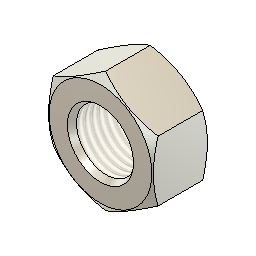
SFX-100 (Autodesk Fusion 360 archive; units mm, degrees)
design "육각 너트 DIN 934 - M12 x 1.25 강 6 플레인"
description: 육각 너트 DIN 934 - M12 x 1.25
part number: DIN 934 - M12 x 1.25 강 6 플레인
Autodesk Fusion 360 part; units mm, degrees
sketch "Sketch1" plane through (0, 0, 0) normal (0, 1, 0) x (1, 0, 0)
  line L0 (0, 0) -> (0, -10)
  line L1 (-6, 0) -> (-9.31, 0)
  line L2 (-9.31, 0) -> (-10.9725, -0.9598)
  line L3 (-10.9725, -0.9598) -> (-10.9725, -9.0402)
  line L4 (-10.9725, -9.0402) -> (-9.31, -10)
  line L5 (-9.31, -10) -> (-6, -10)
  line L6 (-6, -10) -> (-6, 0)
  dimension "d121" = 12
  dimension "d122" = 30
  dimension "d123" = 30
  dimension "d128" = 21.945
  dimension "d172" = 18.62
  dimension "d176" = 10
  constraint vertical L0
  constraint coincident L0 L0.end
  constraint coincident origin L0
  constraint horizontal L1
  constraint perpendicular L1 L3
  constraint perpendicular L3 L5
  constraint perpendicular L5 L6
  constraint coincident L0.start L1
  constraint coincident L0.start origin
  constraint coincident L0.end L5
  constraint vertical L1.end L4.end
  measures "d122" angle of L1 L2
  measures "d123" angle of L4 L5
  measures "d176" distance of L1.start L5
revolve "Revolve1" add sketch "Sketch1" angle 360 about axis through (0, 0, 0) along (0, 0, 1)
sketch "Sketch8" plane through (0, 0, 10) normal (0, 0, 1) x (1, 0, 0)
  line L0 (0, 0) -> (-19, 0) construction
  line L1 (-9.5, -5.4905) -> (-9.5, 5.4905)
  circle A0 centre (0, 0) radius 6
  circle A1 centre (0, 0) radius 10.9725
  dimension "d114" = 9.5
  constraint horizontal L0
  constraint perpendicular L0 L1
  constraint midpoint L0 L1
  constraint coincident L0.start A0.centre
  constraint coincident L1.end A1
  measures "d114" distance of L0.start L1
extrude "Extrude5" cut sketch "Sketch8" against normal blind 10 contours L1 A1 picked at (-9.7376, 1.3373)
pattern_circular "C-Pattern2" count 6 over 360 about axis through (0, 0, 1.75) along (0, 0, 1) of "Extrude5"
thread "Thread3" "ISO Metric profile 12.0 M12x1.25 M12x1.25 6H" major diameter 12.18 minor diameter 10.7795 pitch 1.25 angle 60 resizes the face on face at (-5.9702, 0.5974, 6.6667)
sketch "Sketch12" plane through (0, 0, 0) normal (0, 1, 0) x (1, 0, 0)
  line L0 (5.3898, -10) -> (-5.3898, -10)
  line L1 (9.31, -10) -> (-9.31, -10)
  line L2 (9.31, 0) -> (-9.31, 0)
  line L3 (5.3898, 0) -> (-5.3898, 0)
  line L4 (-6, 0) -> (0, 0)
  line L5 (-3.1132, -5) -> (-6, 0)
  line L6 (-6, -10) -> (0, -10)
  line L7 (-3.1132, -5) -> (-6, -10)
  line L8 (0, 0) -> (0, -10)
  dimension "d165" = 60
  dimension "d169" = 60
  dimension "d177" = 6
  constraint horizontal L4
  constraint collinear L1 L6
  constraint coincident L5.start L7.start
  constraint vertical L4.start L6.start
  constraint coincident L1 L6.end
  constraint coincident L6.end L8.end
  constraint coincident L4.end L8.start
  measures "d165" angle of L2 L5
  measures "d169" angle of L6 L7
  measures "d177" distance of L4.start L8
revolve "Revolve3" cut sketch "Sketch12" angle 360 about axis through (0, 0, 1.75) along (0, 0, 1)
equation "adsk_nheig = 10.00 mm"
equation "adsk_maxdia = 21.945 mm"
equation "adsk_nomdia = 12.00 mm"
equation "d89 = -adsk_nheig"
equation "adsk_waflat = 19.00 mm"
equation "d114 = adsk_waflat / 2"
equation "adsk_chamang1 = 30.00 deg"
equation "adsk_chamang2 = 30.00 deg"
equation "d121 = adsk_nomdia"
equation "d122 = adsk_chamang1"
equation "d123 = adsk_chamang2"
equation "d128 = adsk_maxdia"
equation "d163 = adsk_nheig"
equation "adsk_beardia = adsk_waflat * 0.98"
equation "d172 = adsk_beardia"
equation "d176 = adsk_nheig"
equation "d177 = adsk_nomdia * 0.5"

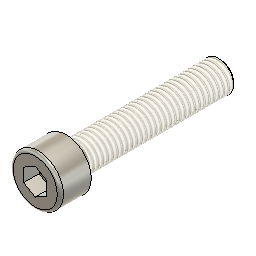
design "브로치 육각 소켓 머리 캡 나사 ANSI B18.3.1M - M8x1.25 x 40 강철 등급 2 플레인"
description: 브로치 육각 소켓 머리 캡 나사 ANSI B18.3.1M - M8x1.25 x 40
part number: BSHCS ANSI B18.3.1M - M8x1.25 x 40 강철 등급 2 플레인
Autodesk Fusion 360 part; units mm, degrees
sketch "Sketch1" plane through (0, 0, 0) normal (0, 1, 0) x (1, 0, 0)
  line L0 (-4, 0) -> (-4, 40)
  line L1 (-4, 40) -> (0, 40)
  line L2 (0, 40) -> (0, -8)
  line L3 (-4, 0) -> (-6.5, 0)
  line L4 (-6.5, 0) -> (-6.5, -8)
  line L5 (-6.5, -8) -> (0, -8)
  dimension "d9" = 8
  dimension "d66" = 13
  dimension "d101" = 40
  dimension "d102" = 8
  constraint perpendicular L0 L1
  constraint collinear origin L1.end L2.end
  constraint perpendicular L0 L3
  constraint coincident origin L3
  constraint vertical L0
  constraint vertical L2
  constraint parallel L2 L4
  constraint coincident L2 L5.end
  constraint perpendicular L2 L5
  measures "d101" distance of origin L1
  measures "d102" distance of L3.end L5
revolve "Revolve1" add sketch "Sketch1" angle 360 about axis through (0, 0, -40) along (0, 0, 1)
ref_plane "WorkPlane1" through (0, 0, 8) normal (0, 0, 1) x (1, 0, 0)
sketch "Sketch6" plane through (0, 0, 8) normal (0, 0, 1) x (1, 0, 0)
  line L0 (-3, 0) -> (3, 0) construction
  line L1 (0, 0) -> (-3, 1.7321)
  line L2 (-3, -1.7321) -> (-3, 1.7321)
  line L3 (-3, -1.7321) -> (0, 0)
  dimension "d100" = 150
  dimension "d103" = 6
  constraint horizontal L0
  constraint midpoint L1.start L0
  constraint coincident L1.start L3.end
  constraint perpendicular L0 L2
  constraint midpoint L0.start L2
  constraint coincident L1.end L2.end
  measures "d100" angle of L0 L1
  measures "d103" distance of L0.end L2
extrude "Extrude1" cut sketch "Sketch6" against normal blind 4
pattern_circular "C-Pattern1" count 6 over 360 about axis through (0, 0, 1.75) along (0, 0, 1) of "Extrude1"
extrude "Extrude2" cut 1 faces at (0, -1.1547, 4) along direction (0, 0, -1) blind 4 draft -85
thread "Thread3" "ANSI Metric M Profile 8.0 M8x1.25 M8x1.25 4g6g" major diameter 7.866 minor diameter 6.467 pitch 1.25 angle 60 resizes the face on face at (-3.9801, 0.3983, -13.3333) from (0, 0, -2.3336) to (0, 0, -40)
fillet "Fillet4" radius 0.8 1 edges at (-6.0601, 2.3505, 8)
sketch "Sketch7" plane through (0, 0, 0) normal (0, 1, 0) x (1, 0, 0)
  line L0 (-4.08, 40) -> (-4.08, 39.2332)
  line L1 (-4.08, 39.2332) -> (-3.2332, 40)
  line L2 (0, 40) -> (0, -8)
  line L3 (-4.08, 40) -> (0, 40)
  dimension "d104" = 3.2332
  dimension "d105" = 4.08
  dimension "d106" = 0.7668
  constraint coincident L2.start L3.end
  constraint perpendicular L2 L3
  constraint coincident L1.end L3
  constraint perpendicular L0 L3
  measures "d104" distance of L1.end L2
  measures "d105" distance of L0 L2.start
  measures "d106" distance of L0.end L3
revolve "Revolve3" cut sketch "Sketch7" angle 360 about axis through (0, 0, 1.75) along (0, 0, 1)
equation "d9 = adsk_nomdia"
equation "adsk_nomlen = 40.00 mm"
equation "adsk_headh = 8.00 mm"
equation "adsk_headdia = 13.00 mm"
equation "adsk_nomdia = 8.00 mm"
equation "adsk_philwidth = 6.00 mm"
equation "d31 = -adsk_phildepth"
equation "adsk_phildepth = 4.00 mm"
equation "d66 = adsk_headdia"
equation "d71 = adsk_headh"
equation "d76 = -adsk_phildepth"
equation "adsk_thrlen = 37.666375 mm"
equation "d86 = adsk_nomdia * 0.1"
equation "adsk_startlen = 0.7668125 mm"
equation "adsk_endpointdia = 6.466375 mm"
equation "d101 = adsk_nomlen"
equation "d102 = adsk_headh"
equation "d103 = adsk_philwidth"
equation "d104 = adsk_endpointdia / 2"
equation "d105 = adsk_nomdia * 0.51"
equation "d106 = adsk_startlen"
equation "d108 = min(adsk_thrlen; adsk_nomlen - 0.001 mm)"

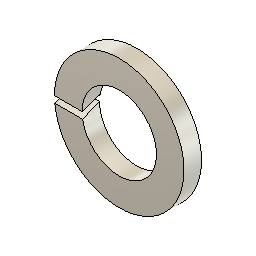
design "스프링 잠금 와셔 DIN 127 - A 8 강 100 HV 플레인"
description: 스프링 잠금 와셔 DIN 127 - A 8
part number: DIN 127 - A 8 강 100 HV 플레인
Autodesk Fusion 360 part; units mm, degrees
sketch "Sketch1" plane through (0, 0, 0) normal (0, 0, 1) x (1, 0, 0)
  circle A0 centre (0, 0) radius 7.4
  circle A1 centre (0, 0) radius 4.25
  dimension "d4" = 14.8
  dimension "d5" = 8.5
  constraint coincident A0.centre A1.centre
  measures "d4" diameter of A0
  measures "d5" diameter of A1
extrude "Extrude1" add sketch "Sketch1" along normal blind 2
ref_plane "WorkPlane1" through (12.125, 0, 0) normal (0, -0.34202, 0.939693) x (1, 0, 0)
ref_plane "WorkPlane2" through (12.125, -0.342, 0.9397) normal (0, -0.34202, 0.939693) x (1, 0, 0)
sketch "Sketch2" plane through (12.125, -0.342, 0.9397) normal (0, -0.34202, 0.939693) x (1, 0, 0)
  ellipse E0 centre (-12.125, 0.684) end of major axis (-4.725, 0.684) minor radius 6.9537
  ellipse E1 centre (-12.125, 0) end of major axis (-4.725, 0) minor radius 6.9537
  line L0 (-12.125, 0.684) -> (-12.125, 0)
  line L1 (-12.125, 0.684) -> (-19.821, 0.684)
  line L2 (-12.125, 0) -> (-19.821, 0)
  line L3 (-19.821, 0) -> (-19.821, 0.684)
  dimension "d36" = 7.696
  constraint coincident E0.centre L0.start
  constraint coincident E1.centre L0.end
  constraint perpendicular L0 L1
  constraint perpendicular L0 L2
  measures "d36" distance of L0 L3
extrude "Extrude2" cut sketch "Sketch2" along normal through all and the other way through all contours E0 E1 L1 | E0 E1 L1 L2 L3 | E0 E1 L0 L1 L2 | E0 E1 L2 picked at (-19.5039, 0.6556) picked at (-17.0344, 0.456) picked at (-19.5039, 0.0285)
equation "adsk_woutdia = 14.80 mm"
equation "adsk_windia = 8.50 mm"
equation "adsk_wthick = 2.00 mm"
equation "d4 = adsk_woutdia"
equation "d5 = adsk_windia"
equation "d6 = adsk_wthick"
equation "d13 = adsk_wthick / 2"
equation "d34 = adsk_wthick"
equation "d36 = adsk_woutdia * 0.52"

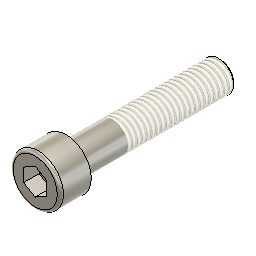
design "육각 소켓 머리 캡 나사 DIN 912 - M8 x 1.25 x 40 강 4.6 플레인"
description: 육각 소켓 머리 캡 나사 DIN 912 - M8 x 1.25 x 40
part number: DIN 912 - M8 x 1.25 x 40 강 4.6 플레인
Autodesk Fusion 360 part; units mm, degrees
sketch "Sketch1" plane through (0, 0, 0) normal (0, 1, 0) x (1, 0, 0)
  line L0 (-4, 0) -> (-4, 40)
  line L1 (-4, 40) -> (0, 40)
  line L2 (0, 40) -> (0, -8)
  line L3 (-4, 0) -> (-6.5, 0)
  line L4 (-6.5, 0) -> (-6.5, -8)
  line L5 (-6.5, -8) -> (0, -8)
  dimension "d9" = 8
  dimension "d66" = 13
  dimension "d101" = 40
  dimension "d102" = 8
  constraint perpendicular L0 L1
  constraint collinear origin L1.end L2.end
  constraint perpendicular L0 L3
  constraint coincident origin L3
  constraint vertical L0
  constraint vertical L2
  constraint parallel L2 L4
  constraint coincident L2 L5.end
  constraint perpendicular L2 L5
  measures "d101" distance of origin L1
  measures "d102" distance of L3.end L5
revolve "Revolve1" add sketch "Sketch1" angle 360 about axis through (0, 0, -40) along (0, 0, 1)
ref_plane "WorkPlane1" through (0, 0, 8) normal (0, 0, 1) x (1, 0, 0)
sketch "Sketch6" plane through (0, 0, 8) normal (0, 0, 1) x (1, 0, 0)
  line L0 (-3, 0) -> (3, 0) construction
  line L1 (0, 0) -> (-3, 1.7321)
  line L2 (-3, -1.7321) -> (-3, 1.7321)
  line L3 (-3, -1.7321) -> (0, 0)
  dimension "d100" = 150
  dimension "d103" = 6
  constraint horizontal L0
  constraint midpoint L1.start L0
  constraint coincident L1.start L3.end
  constraint perpendicular L0 L2
  constraint midpoint L0.start L2
  constraint coincident L1.end L2.end
  measures "d100" angle of L0 L1
  measures "d103" distance of L0.end L2
extrude "Extrude1" cut sketch "Sketch6" against normal blind 4
pattern_circular "C-Pattern1" count 6 over 360 about axis through (0, 0, 1.75) along (0, 0, 1) of "Extrude1"
extrude "Extrude2" cut 1 faces at (0, -1.1547, 4) along direction (0, 0, -1) blind 4 draft -85
thread "Thread3" "ISO Metric profile 8.0 M8x1.25 M8x1.25 6g" major diameter 7.866 minor diameter 6.4455 pitch 1.25 angle 60 resizes the face on face at (-3.995, 0.1994, -26.6667) from (0, 0, -12) to (0, 0, -40)
fillet "Fillet4" radius 0.8 1 edges at (-6.0601, 2.3505, 8)
sketch "Sketch7" plane through (0, 0, 0) normal (0, 1, 0) x (1, 0, 0)
  line L0 (-4.08, 40) -> (-4.08, 39.2332)
  line L1 (-4.08, 39.2332) -> (-3.2332, 40)
  line L2 (0, 40) -> (0, -8)
  line L3 (-4.08, 40) -> (0, 40)
  dimension "d104" = 3.2332
  dimension "d105" = 4.08
  dimension "d106" = 0.7668
  constraint coincident L2.start L3.end
  constraint perpendicular L2 L3
  constraint coincident L1.end L3
  constraint perpendicular L0 L3
  measures "d104" distance of L1.end L2
  measures "d105" distance of L0 L2.start
  measures "d106" distance of L0.end L3
revolve "Revolve3" cut sketch "Sketch7" angle 360 about axis through (0, 0, 1.75) along (0, 0, 1)
equation "d9 = adsk_nomdia"
equation "adsk_nomlen = 40.00 mm"
equation "adsk_headh = 8.00 mm"
equation "adsk_headdia = 13.00 mm"
equation "adsk_nomdia = 8.00 mm"
equation "adsk_philwidth = 6.00 mm"
equation "d31 = -adsk_phildepth"
equation "adsk_phildepth = 4.00 mm"
equation "d66 = adsk_headdia"
equation "d71 = adsk_headh"
equation "d76 = -adsk_phildepth"
equation "adsk_thrlen = 28.00 mm"
equation "d86 = adsk_nomdia * 0.1"
equation "adsk_startlen = 0.7668125 mm"
equation "adsk_endpointdia = 6.466375 mm"
equation "d101 = adsk_nomlen"
equation "d102 = adsk_headh"
equation "d103 = adsk_philwidth"
equation "d104 = adsk_endpointdia / 2"
equation "d105 = adsk_nomdia * 0.51"
equation "d106 = adsk_startlen"
equation "d108 = min(adsk_thrlen; adsk_nomlen - 0.001 mm)"

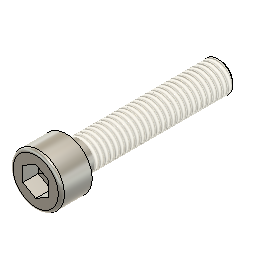
design "육각 소켓 머리 캡 나사 DIN 912 - M6 x 1 x 30 강 4.6 플레인"
description: 육각 소켓 머리 캡 나사 DIN 912 - M6 x 1 x 30
part number: DIN 912 - M6 x 1 x 30 강 4.6 플레인
Autodesk Fusion 360 part; units mm, degrees
sketch "Sketch1" plane through (0, 0, 0) normal (0, 1, 0) x (1, 0, 0)
  line L0 (-3, 0) -> (-3, 30)
  line L1 (-3, 30) -> (0, 30)
  line L2 (0, 30) -> (0, -6)
  line L3 (-3, 0) -> (-5, 0)
  line L4 (-5, 0) -> (-5, -6)
  line L5 (-5, -6) -> (0, -6)
  dimension "d9" = 6
  dimension "d66" = 10
  dimension "d101" = 30
  dimension "d102" = 6
  constraint perpendicular L0 L1
  constraint collinear origin L1.end L2.end
  constraint perpendicular L0 L3
  constraint coincident origin L3
  constraint vertical L0
  constraint vertical L2
  constraint parallel L2 L4
  constraint coincident L2 L5.end
  constraint perpendicular L2 L5
  measures "d101" distance of origin L1
  measures "d102" distance of L3.end L5
revolve "Revolve1" add sketch "Sketch1" angle 360 about axis through (0, 0, -30) along (0, 0, 1)
ref_plane "WorkPlane1" through (0, 0, 6) normal (0, 0, 1) x (1, 0, 0)
sketch "Sketch6" plane through (0, 0, 6) normal (0, 0, 1) x (1, 0, 0)
  line L0 (-2.5, 0) -> (2.5, 0) construction
  line L1 (0, 0) -> (-2.5, 1.4434)
  line L2 (-2.5, -1.4434) -> (-2.5, 1.4434)
  line L3 (-2.5, -1.4434) -> (0, 0)
  dimension "d100" = 150
  dimension "d103" = 5
  constraint horizontal L0
  constraint midpoint L1.start L0
  constraint coincident L1.start L3.end
  constraint perpendicular L0 L2
  constraint midpoint L0.start L2
  constraint coincident L1.end L2.end
  measures "d100" angle of L0 L1
  measures "d103" distance of L0.end L2
extrude "Extrude1" cut sketch "Sketch6" against normal blind 3
pattern_circular "C-Pattern1" count 6 over 360 about axis through (0, 0, 1.75) along (0, 0, 1) of "Extrude1"
extrude "Extrude2" cut 1 faces at (0, 0.9623, 3) along direction (0, 0, -1) blind 3 draft -85
thread "Thread3" "ISO Metric profile 6.0 M6x1 M6x1 6g" major diameter 5.884 minor diameter 4.7435 pitch 1 angle 60 resizes the face on face at (-2.9963, 0.1495, -10) from (0, 0, -2.5) to (0, 0, -30)
fillet "Fillet4" radius 0.6 1 edges at (-4.6616, 1.8081, 6)
sketch "Sketch7" plane through (0, 0, 0) normal (0, 1, 0) x (1, 0, 0)
  line L0 (-3.06, 30) -> (-3.06, 29.3866)
  line L1 (-3.06, 29.3866) -> (-2.3865, 30)
  line L2 (0, 30) -> (0, -6)
  line L3 (-3.06, 30) -> (0, 30)
  dimension "d104" = 2.3866
  dimension "d105" = 3.06
  dimension "d106" = 0.6135
  constraint coincident L2.start L3.end
  constraint perpendicular L2 L3
  constraint coincident L1.end L3
  constraint perpendicular L0 L3
  measures "d104" distance of L1.end L2
  measures "d105" distance of L0 L2.start
  measures "d106" distance of L0.end L3
revolve "Revolve3" cut sketch "Sketch7" angle 360 about axis through (0, 0, 1.75) along (0, 0, 1)
equation "d9 = adsk_nomdia"
equation "adsk_nomlen = 30.00 mm"
equation "adsk_headh = 6.00 mm"
equation "adsk_headdia = 10.00 mm"
equation "adsk_nomdia = 6.00 mm"
equation "adsk_philwidth = 5.00 mm"
equation "d31 = -adsk_phildepth"
equation "adsk_phildepth = 3.00 mm"
equation "d66 = adsk_headdia"
equation "d71 = adsk_headh"
equation "d76 = -adsk_phildepth"
equation "adsk_thrlen = 27.50 mm"
equation "d86 = adsk_nomdia * 0.1"
equation "adsk_startlen = 0.61345 mm"
equation "adsk_endpointdia = 4.7731 mm"
equation "d101 = adsk_nomlen"
equation "d102 = adsk_headh"
equation "d103 = adsk_philwidth"
equation "d104 = adsk_endpointdia / 2"
equation "d105 = adsk_nomdia * 0.51"
equation "d106 = adsk_startlen"
equation "d108 = min(adsk_thrlen; adsk_nomlen - 0.001 mm)"
